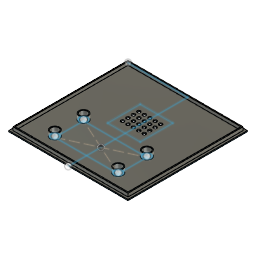
Inverter case top (Autodesk Fusion 360 design; units mm, degrees)
Autodesk Fusion 360 part; units mm, degrees
note: some values were not read from the file. Set by a fixed rule: which face or edge a step refers to.
sketch "Sketch1" plane through (0, 0, 0) normal (0, 0, 1) x (1, 0, 0)
  line L0 (0, 0) -> (110, 0)
  line L1 (110, 0) -> (110, 110)
  line L2 (110, 110) -> (0, 110)
  line L3 (0, 110) -> (0, 0)
  dimension "d1" = 110
  dimension "d2" = 110
  constraint horizontal L0
  constraint vertical L1
  constraint horizontal L2
  constraint vertical L3
  constraint coincident L0.start L3.end
  measures "d1" distance of L0.start L0.end
  measures "d2" distance of L0.start L2.end
extrude "Extrude1" add sketch "Sketch1" along normal blind 1
sketch "Sketch2" plane through (0, 0, 1) normal (0, 0, 1) x (-1, 0, 0)
  line L0 (0, -110) -> (0, 0)
  line L1 (0, 0) -> (-110, 0)
  line L2 (-110, 0) -> (-110, -110)
  line L3 (-110, -110) -> (0, -110)
  line L4 (-107.5, -2.5) -> (-2.5, -2.5)
  line L5 (-2.5, -2.5) -> (-2.5, -107.5)
  line L6 (-2.5, -107.5) -> (-107.5, -107.5)
  line L7 (-107.5, -107.5) -> (-107.5, -2.5)
  line L8 (-107.5, -2.5) -> (-2.5, -107.5) construction
  line L9 (-2.5, -2.5) -> (-107.5, -107.5) construction
  point P0 (-55, -55)
  dimension "d5" = 105
  dimension "d6" = 105
  constraint horizontal L4
  constraint perpendicular L4 L5
  constraint parallel L4 L6
  constraint parallel L5 L7
  constraint coincident L8 P0
  constraint coincident L9 P0
  measures "d5" distance of L5.end L6.end
  measures "d6" distance of L4.end L5.end
extrude "Extrude2" add sketch "Sketch2" along normal blind 1 contours L4 L5 L6 L7
sketch "Sketch3" plane through (0, 0, 2) normal (0, 0, 1) x (-1, 0, 0)
  line L0 (-107.5, -107.5) -> (-2.5, -107.5)
  line L1 (-2.5, -107.5) -> (-2.5, -2.5)
  line L2 (-2.5, -2.5) -> (-107.5, -2.5)
  line L3 (-107.5, -2.5) -> (-107.5, -107.5)
  line L4 (-55, 0) -> (-55, -110)
  line L5 (0, -55) -> (-110, -55)
  line L6 (-55, 0) -> (-82.5, 0)
  line L7 (-82.5, 0) -> (-82.5, -110)
  line L8 (0, -55) -> (0, -82.5)
  line L9 (0, -82.5) -> (-110, -82.5)
  line L10 (-110, -82.5) -> (-110, -68.75)
  line L11 (-110, -68.75) -> (0, -68.75)
  line L12 (-55, 0) -> (-68.75, 0)
  line L13 (-68.75, 0) -> (-68.75, -110)
  dimension "d9" = 27.5
  dimension "d10" = 27.5
  dimension "d11" = 13.75
  constraint perpendicular L0 L4
  constraint perpendicular L3 L5
  constraint perpendicular L4 L6
  constraint perpendicular L0 L7
  constraint perpendicular L0 L8
  constraint perpendicular L3 L9
  constraint perpendicular L5 L10
  constraint midpoint L8 L11.end
  constraint midpoint L6 L12.end
  constraint perpendicular L0 L13
  measures "d9" distance of L4.start L6.end
  measures "d10" distance of L5.start L8.end
  measures "d11" distance of L9.end L10.end
sketch "Sketch4" plane through (0, 0, 0) normal (0, 0, -1) x (1, 0, 0)
  line L0 (0, 0) -> (0, -110)
  line L1 (0, -110) -> (110, -110)
  line L2 (110, -110) -> (110, 0)
  line L3 (110, 0) -> (0, 0)
  line L4 (68.75, -82.5) -> (38.75, -82.5)
  line L5 (38.75, -82.5) -> (38.75, -52.5)
  line L6 (38.75, -52.5) -> (68.75, -52.5)
  line L7 (68.75, -52.5) -> (68.75, -82.5)
  dimension "d12" = 30
  dimension "d13" = 30
  constraint horizontal L4
  constraint vertical L5
  constraint horizontal L6
  constraint vertical L7
  measures "d12" distance of L4.start L4.end
  measures "d13" distance of L4.start L6.end
sketch "Sketch5" plane through (0, 0, 0) normal (0, 0, -1) x (1, 0, 0)
  circle A0 centre (45, -60) radius 1.5
  circle A1 centre (50, -60) radius 1.5
  circle A2 centre (55, -60) radius 1.5
  circle A3 centre (60, -60) radius 1.5
  circle A4 centre (65, -60) radius 1.5
  circle A5 centre (45, -65) radius 1.5
  circle A6 centre (50, -65) radius 1.5
  circle A7 centre (55, -65) radius 1.5
  circle A8 centre (60, -65) radius 1.5
  circle A9 centre (65, -65) radius 1.5
  circle A10 centre (45, -70) radius 1.5
  circle A11 centre (50, -70) radius 1.5
  circle A12 centre (55, -70) radius 1.5
  circle A13 centre (60, -70) radius 1.5
  circle A14 centre (65, -70) radius 1.5
  circle A15 centre (45, -75) radius 1.5
  circle A16 centre (50, -75) radius 1.5
  circle A17 centre (55, -75) radius 1.5
  circle A18 centre (60, -75) radius 1.5
  circle A19 centre (65, -75) radius 1.5
  dimension "d14" = 3
  dimension "d15" = 3
  dimension "d16" = 3
  dimension "d17" = 3
  dimension "d18" = 3
  dimension "d19" = 3
  dimension "d20" = 3
  dimension "d21" = 3
  dimension "d22" = 3
  dimension "d23" = 3
  dimension "d24" = 3
  dimension "d25" = 3
  dimension "d26" = 3
  dimension "d27" = 3
  dimension "d28" = 3
  dimension "d29" = 3
  dimension "d30" = 3
  dimension "d31" = 3
  dimension "d32" = 3
  dimension "d33" = 3
  measures "d14" diameter of A0
  measures "d15" diameter of A1
  measures "d16" diameter of A2
  measures "d17" diameter of A3
  measures "d18" diameter of A4
  measures "d19" diameter of A5
  measures "d20" diameter of A6
  measures "d21" diameter of A7
  measures "d22" diameter of A8
  measures "d23" diameter of A9
  measures "d24" diameter of A10
  measures "d25" diameter of A11
  measures "d26" diameter of A12
  measures "d27" diameter of A13
  measures "d28" diameter of A14
  measures "d29" diameter of A15
  measures "d30" diameter of A16
  measures "d31" diameter of A17
  measures "d32" diameter of A18
  measures "d33" diameter of A19
extrude "Extrude3" cut sketch "Sketch5" against normal blind 8765785
extrude "Extrude4" cut sketch "Sketch3" against normal blind 1 contours L0 L3 L7 L9 | L0 L7 L9 L13 | L3 L7 L9 L11 | L0 L4 L9 L13 | L7 L9 L11 L13 | L3 L5 L7 L11 | L0 L1 L4 L9 | L4 L9 L11 L13 | L5 L7 L11 L13 | L2 L3 L5 L7 | L1 L4 L9 L11 | L4 L5 L11 L13 | L2 L5 L7 L13 | L1 L4 L5 L11 | L2 L4 L5 L13 | L1 L2 L4 L5
sketch "Sketch6" plane through (0, 0, 1) normal (0, 0, 1) x (-1, 0, 0)
  circle A0 centre (-55, -75) radius 1.5
  circle A1 centre (-50, -70) radius 1.5
  circle A2 centre (-65, -65) radius 1.5
  circle A3 centre (-45, -65) radius 1.5
  circle A4 centre (-50, -60) radius 1.5
  circle A5 centre (-55, -60) radius 1.5
  circle A6 centre (-50, -65) radius 1.5
  circle A7 centre (-65, -70) radius 1.5
  circle A8 centre (-45, -70) radius 1.5
  circle A9 centre (-60, -75) radius 1.5
  circle A10 centre (-50, -75) radius 1.5
  circle A11 centre (-55, -70) radius 1.5
  circle A12 centre (-60, -65) radius 1.5
  circle A13 centre (-65, -60) radius 1.5
  circle A14 centre (-45, -60) radius 1.5
  circle A15 centre (-60, -60) radius 1.5
  circle A16 centre (-55, -65) radius 1.5
  circle A17 centre (-60, -70) radius 1.5
  circle A18 centre (-45, -75) radius 1.5
  circle A19 centre (-65, -75) radius 1.5
  line L0 (0, -110) -> (0, 0)
  line L1 (0, 0) -> (-110, 0)
  line L2 (-110, 0) -> (-110, -110)
  line L3 (-110, -110) -> (0, -110)
  line L4 (-108, -2) -> (-2, -2)
  line L5 (-2, -2) -> (-2, -108)
  line L6 (-2, -108) -> (-108, -108)
  line L7 (-108, -108) -> (-108, -2)
  line L8 (-108, -2) -> (-2, -108) construction
  line L9 (-2, -2) -> (-108, -108) construction
  point P0 (-55, -55)
  dimension "d38" = 106
  dimension "d39" = 106
  constraint horizontal L4
  constraint perpendicular L4 L5
  constraint parallel L4 L6
  constraint parallel L5 L7
  constraint coincident L8 P0
  constraint coincident L9 P0
  measures "d38" distance of L5.end L6.end
  measures "d39" distance of L4.end L5.end
extrude "Extrude5" add sketch "Sketch6" along normal blind 3 contours L4 L5 L6 L7
shell "Shell1" thickness 1 removed faces 1 at (55, 20.8333, 4)
extrude "Extrude6" cut 20 faces at (65.1596, 72.8438, 4) (65.4811, 72.1078, 4) (66.7863, 66.2179, 4) (65.1596, 62.1562, 4) (57.8482, 59.8013, 4) (60.156, 62.8432, 4) (60.156, 67.8432, 4) (61.6659, 76.3763, 4) (56.6659, 76.3763, 4) (55.156, 67.8432, 4) (55.156, 62.8432, 4) (52.8482, 59.8013, 4) (47.8482, 59.8013, 4) (50.156, 62.8432, 4) (50.156, 72.1568, 4) (51.6659, 76.3763, 4) (44.8404, 72.8438, 4) (43.652, 71.6903, 4) (44.2101, 67.0126, 4) (44.8404, 62.1562, 4) along direction (0, 0, -1) blind 3
sketch "Sketch7" plane through (0, 0, 0) normal (0, 0, -1) x (1, 0, 0)
  line L0 (0, -110) -> (55, -110)
  line L1 (55, -110) -> (55, 0)
  line L2 (25.85, -16.85) -> (84.15, -16.85)
  line L3 (84.15, -16.85) -> (84.15, -43.25)
  line L4 (84.15, -43.25) -> (25.85, -43.25)
  line L5 (25.85, -43.25) -> (25.85, -16.85)
  line L6 (25.85, -16.85) -> (84.15, -43.25) construction
  line L7 (84.15, -16.85) -> (25.85, -43.25) construction
  point P0 (55, -30.05)
  dimension "d45" = 55
  dimension "d46" = 58.3
  dimension "d47" = 26.4
  constraint horizontal L0
  constraint perpendicular L0 L1
  constraint horizontal L2
  constraint perpendicular L2 L3
  constraint parallel L2 L4
  constraint parallel L3 L5
  constraint coincident L6 P0
  constraint coincident L7 P0
  constraint coincident L1 P0
  measures "d45" distance of L0.start L0.end
  measures "d46" distance of L3.end L4.end
  measures "d47" distance of L2.end L3.end
sketch "Sketch8" plane through (0, 0, 0) normal (0, 0, -1) x (1, 0, 0)
  circle A0 centre (84.15, -43.25) radius 1.7
  circle A1 centre (25.85, -43.25) radius 1.7
  circle A2 centre (25.85, -16.85) radius 1.7
  circle A3 centre (84.15, -16.85) radius 1.7
  dimension "d48" = 3.4
  dimension "d49" = 3.4
  dimension "d50" = 3.4
  dimension "d51" = 3.4
  measures "d48" diameter of A0
  measures "d49" diameter of A1
  measures "d50" diameter of A2
  measures "d51" diameter of A3
extrude "Extrude7" cut sketch "Sketch8" against normal blind 1
sketch "Sketch9" plane through (0, 0, 1) normal (0, 0, 1) x (-1, 0, 0)
  circle A0 centre (-55, -75) radius 1.5
  circle A1 centre (-45, -75) radius 1.5
  circle A2 centre (-60, -65) radius 1.5
  circle A3 centre (-50, -70) radius 1.5
  circle A4 centre (-55, -60) radius 1.5
  circle A5 centre (-45, -60) radius 1.5
  circle A6 centre (-50, -60) radius 1.5
  line L0 (-107, -107) -> (-3, -107)
  line L1 (-3, -107) -> (-3, -3)
  line L2 (-3, -3) -> (-107, -3)
  line L3 (-107, -3) -> (-107, -107)
  circle A7 centre (-45, -65) radius 1.5
  circle A8 centre (-50, -65) radius 1.5
  circle A9 centre (-45, -70) radius 1.5
  circle A10 centre (-55, -65) radius 1.5
  circle A11 centre (-60, -60) radius 1.5
  circle A12 centre (-50, -75) radius 1.5
  circle A13 centre (-60, -70) radius 1.5
  circle A14 centre (-55, -70) radius 1.5
  circle A15 centre (-65, -60) radius 1.5
  circle A16 centre (-65, -65) radius 1.5
  circle A17 centre (-65, -70) radius 1.5
  circle A18 centre (-60, -75) radius 1.5
  circle A19 centre (-65, -75) radius 1.5
  circle A20 centre (-84.15, -16.85) radius 1.7
  circle A21 centre (-84.15, -43.25) radius 1.7
  circle A22 centre (-25.85, -16.85) radius 1.7
  circle A23 centre (-25.85, -43.25) radius 1.7
  circle A24 centre (-84.15, -16.85) radius 4.25
  circle A25 centre (-25.85, -16.85) radius 4.25
  circle A26 centre (-25.85, -43.25) radius 4.25
  circle A27 centre (-84.15, -43.25) radius 4.25
  dimension "d54" = 8.5
  dimension "d55" = 8.5
  dimension "d56" = 8.5
  dimension "d57" = 8.5
  constraint concentric A20 A24
  constraint concentric A22 A25
  constraint concentric A23 A26
  constraint concentric A21 A27
  measures "d54" diameter of A24
  measures "d55" diameter of A25
  measures "d56" diameter of A26
  measures "d57" diameter of A27
sketch "Sketch10" plane through (0, 0, 1) normal (0, 0, 1) x (-1, 0, 0)
  circle A0 centre (-84.15, -16.85) radius 3.25
  circle A1 centre (-25.85, -16.85) radius 3.25
  circle A2 centre (-25.85, -43.25) radius 3.25
  circle A3 centre (-84.15, -43.25) radius 3.25
  dimension "d58" = 6.5
  dimension "d59" = 6.5
  dimension "d60" = 6.5
  dimension "d61" = 6.5
  measures "d58" diameter of A0
  measures "d59" diameter of A1
  measures "d60" diameter of A2
  measures "d61" diameter of A3
extrude "Extrude8" add sketch "Sketch9" along normal blind 5 contours A24 | A25 | A26 | A27
sketch "Sketch11" plane through (0, 0, 1) normal (0, 0, 1) x (-1, 0, 0)
  circle A0 centre (-84.15, -16.85) radius 3.45
  circle A1 centre (-25.85, -16.85) radius 3.45
  circle A2 centre (-25.85, -43.25) radius 3.45
  circle A3 centre (-84.15, -43.25) radius 3.45
  dimension "d64" = 6.9
  dimension "d65" = 6.9
  dimension "d66" = 6.9
  dimension "d67" = 6.9
  measures "d64" diameter of A0
  measures "d65" diameter of A1
  measures "d66" diameter of A2
  measures "d67" diameter of A3
sketch "Sketch12" plane through (0, 0, 6) normal (0, 0, 1) x (-1, 0, 0)
  circle A0 centre (-25.85, -16.85) radius 1.7
  circle A1 centre (-25.85, -16.85) radius 4.25
  circle A2 centre (-84.15, -16.85) radius 3.45
  circle A3 centre (-25.85, -16.85) radius 3.45
  circle A4 centre (-25.85, -43.25) radius 3.45
  circle A5 centre (-84.15, -43.25) radius 3.45
  dimension "d68" = 6.9
  dimension "d69" = 6.9
  dimension "d70" = 6.9
  dimension "d71" = 6.9
  constraint concentric A0 A3
  measures "d68" diameter of A2
  measures "d69" diameter of A3
  measures "d70" diameter of A4
  measures "d71" diameter of A5
extrude "Extrude9" cut sketch "Sketch12" against normal blind 5 contours A2 | A3 | A4 | A5
equation "d9 = ( 55 / 2 ) * 1 mm"
equation "d10 = ( 55 / 2 ) * 1 mm"
equation "d11 = ( 27.5 / 2 ) * 1 mm"
equation "d54 = 6.5 mm + 2 mm"
